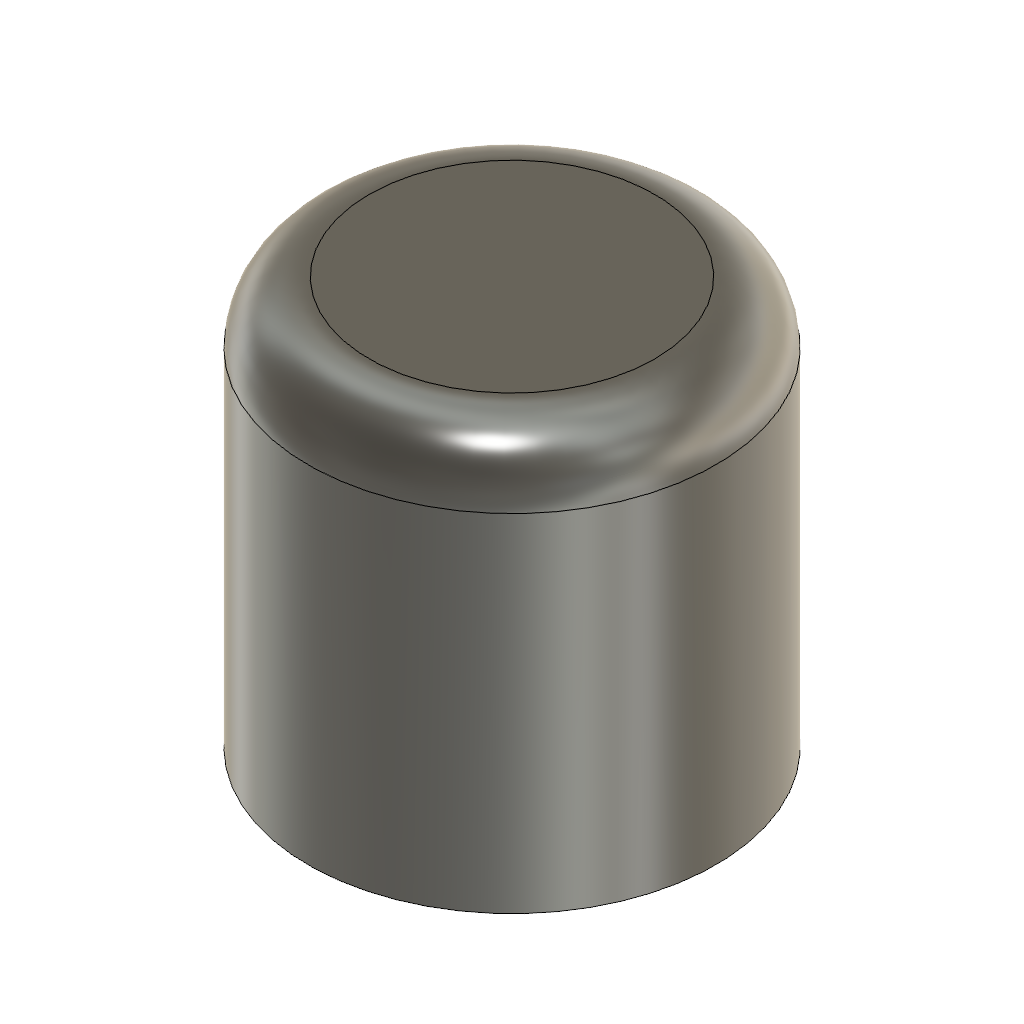
FilletRim (Autodesk Fusion 360 design; units mm, degrees)
part number: 2026-11-12-20-32-25-084
Autodesk Fusion 360 part; units mm, degrees
sketch "Disc sketch" plane through (0, 0, 0) normal (0, 0, 1) x (1, 0, 0)
  circle A0 centre (0, 0) radius 10
extrude "Disc extrude" add sketch "Disc sketch" along normal blind 20
fillet "Rim round" radius 3 1 edges at (-9.3233, -3.6162, 20)
